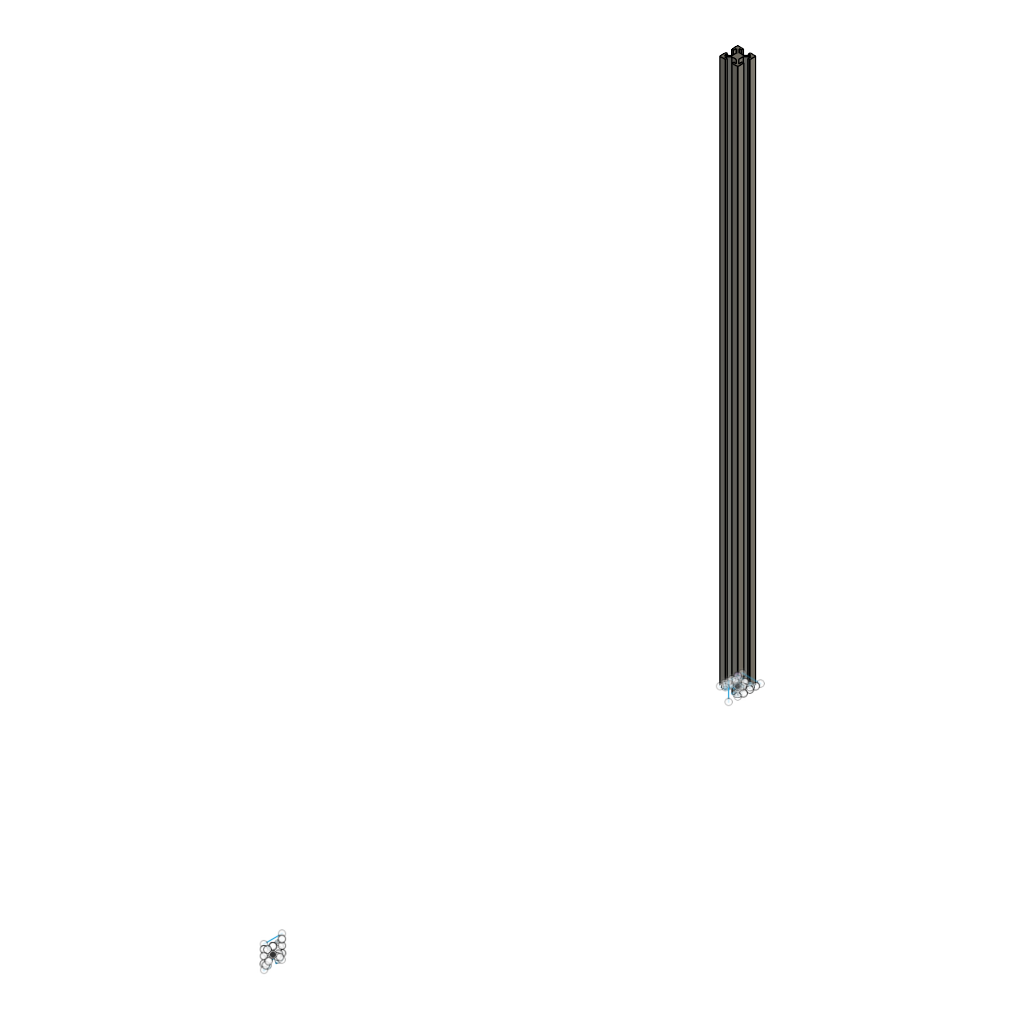
Ensamblaje_TFG (Autodesk Fusion 360 archive; units mm, degrees)
design "Perfilaluminio_23_10_26"
part number: 2026-10-23-16-22-29-947
Autodesk Fusion 360 part; units mm, degrees
sketch "Boceto1" plane through (0, 0, 0) normal (0, 0, 1) x (1, 0, 0)
  line L0 (0, 5) -> (20, 5)
  line L1 (0, -19.75) -> (0, -14.65)
  line L2 (0.25, -20) -> (6.35, -20)
  arc A0 (10, -7.5) -> (10, -12.5) centre (10, -10) ccw
  line L3 (10, -10) -> (10, -7.5) construction
  line L4 (10, -10) -> (10, -12.5) construction
  line L5 (4.1036, -18) -> (6.35, -18)
  line L6 (0, -5.35) -> (0, -6.65)
  arc A1 (0, -6.65) -> (0.25, -6.9) centre (0.25, -6.65) ccw
  line L7 (0, -14.65) -> (0, -13.35)
  arc A2 (0.25, -13.1) -> (0, -13.35) centre (0.25, -13.35) ccw
  line L8 (10, -14) -> (7.5, -14)
  line L9 (10, -6) -> (7.5, -6)
  line L10 (0.25, -6.9) -> (2, -6.9)
  line L11 (0.25, -13.1) -> (2, -13.1)
  line L12 (10, -6) -> (10, -7.5)
  line L13 (10, -12.5) -> (10, -14)
  line L14 (4.1036, -2) -> (6.35, -2)
  line L15 (10, -2) -> (10.0544, -2)
  line L16 (7.5, -10) -> (7.5, -7.5)
  line L17 (7.5, -14) -> (5.4224, -14) construction
  line L18 (6.35, -12.5) -> (5.0376, -12.5) construction
  line L19 (6.35, -2) -> (6.35, 0)
  line L20 (6.35, -20) -> (6.35, -18)
  line L21 (6.35, -12.5) -> (6.35, -7.5)
  line L22 (7.5, -6) -> (3.9268, -2.4268)
  line L23 (7.5, -6) -> (17.1311, -6) construction
  line L24 (6.35, -7.5) -> (2.4268, -3.5768)
  line L25 (6.35, -7.5) -> (15.0863, -7.5) construction
  line L26 (6.35, -12.5) -> (2.4268, -16.4232)
  line L27 (6.35, -12.5) -> (16.6151, -12.5) construction
  line L28 (7.5, -14) -> (3.9268, -17.5732)
  line L29 (7.5, -14) -> (-0.3236, -14) construction
  arc A3 (2.4268, -3.5768) -> (2, -3.7536) centre (2.25, -3.7536) ccw
  arc A4 (4.1036, -2) -> (3.9268, -2.4268) centre (4.1036, -2.25) ccw
  line L30 (2, -3.7536) -> (2, -6.9)
  line L31 (2, -13.1) -> (2, -16.2464)
  arc A5 (2, -16.2464) -> (2.4268, -16.4232) centre (2.25, -16.2464) ccw
  arc A6 (3.9268, -17.5732) -> (4.1036, -18) centre (4.1036, -17.75) ccw
  line L32 (6.35, 0) -> (0.25, 0)
  line L33 (0, -0.25) -> (0, -5.35)
  arc A7 (0.25, 0) -> (0, -0.25) centre (0.25, -0.25) ccw
  arc A8 (0, -19.75) -> (0.25, -20) centre (0.25, -19.75) ccw
  arc A9 (16.0732, -2.4268) -> (15.8964, -2) centre (15.8964, -2.25) ccw
  line L34 (20, -19.75) -> (20, -14.65)
  line L35 (20, -5.35) -> (20, -6.65)
  line L36 (13.65, -7.5) -> (17.5732, -3.5768)
  line L37 (10, -12.5) -> (10, -14)
  line L38 (10, -10) -> (10, -7.5) construction
  line L39 (13.65, 0) -> (19.75, 0)
  line L40 (10, -6) -> (10, -7.5)
  line L41 (10, -10) -> (10, -12.5) construction
  line L42 (12.5, -10) -> (12.5, -7.5)
  line L43 (10, -2) -> (9.9456, -2)
  line L44 (12.5, -14) -> (14.5776, -14) construction
  line L45 (12.5, -6) -> (16.0732, -2.4268)
  line L46 (15.8964, -2) -> (13.65, -2)
  arc A10 (19.75, -20) -> (20, -19.75) centre (19.75, -19.75) ccw
  line L47 (20, -14.65) -> (20, -13.35)
  arc A11 (20, -0.25) -> (19.75, 0) centre (19.75, -0.25) ccw
  arc A12 (19.75, -6.9) -> (20, -6.65) centre (19.75, -6.65) ccw
  arc A13 (17.5732, -16.4232) -> (18, -16.2464) centre (17.75, -16.2464) ccw
  line L48 (19.75, -20) -> (13.65, -20)
  line L49 (13.65, -20) -> (13.65, -18)
  arc A14 (18, -3.7536) -> (17.5732, -3.5768) centre (17.75, -3.7536) ccw
  arc A15 (15.8964, -18) -> (16.0732, -17.5732) centre (15.8964, -17.75) ccw
  line L50 (19.75, -6.9) -> (18, -6.9)
  line L51 (18, -13.1) -> (18, -16.2464)
  line L52 (13.65, -12.5) -> (14.9624, -12.5) construction
  line L53 (13.65, -2) -> (13.65, 0)
  line L54 (15.8964, -18) -> (13.65, -18)
  line L55 (18, -3.7536) -> (18, -6.9)
  line L56 (13.65, -12.5) -> (13.65, -7.5)
  line L57 (12.5, -14) -> (16.0732, -17.5732)
  line L58 (19.75, -13.1) -> (18, -13.1)
  arc A16 (20, -13.35) -> (19.75, -13.1) centre (19.75, -13.35) ccw
  line L59 (20, -0.25) -> (20, -5.35)
  line L60 (12.5, -6) -> (2.8689, -6) construction
  line L61 (10, -14) -> (12.5, -14)
  line L62 (12.5, -14) -> (20.3236, -14) construction
  line L63 (10, -6) -> (12.5, -6)
  line L64 (13.65, -12.5) -> (3.3849, -12.5) construction
  line L65 (13.65, -7.5) -> (4.9137, -7.5) construction
  arc A17 (10, -12.5) -> (10, -7.5) centre (10, -10) ccw
  line L66 (13.65, -12.5) -> (17.5732, -16.4232)
  point P0 (0, -6.35)
  point P1 (20, -6.35)
  point P2 (20, 0)
  dimension "d2" = 6.35
  dimension "d3" = 20
  dimension "d16" = 2.5
  dimension "d17" = 180
  dimension "d27" = 0.25
  dimension "d34" = 135
  dimension "d35" = 135
  dimension "d36" = 135
  dimension "d37" = 45
  dimension "d38" = 0.25
  dimension "d39" = 0.25
  dimension "d40" = 0.25
  dimension "d41" = 0.25
  dimension "d42" = 0.25
  dimension "d43" = 0.25
  constraint vertical L1
  constraint perpendicular L1 L2
  constraint perpendicular L2 L31
  constraint perpendicular L14 L30
  constraint perpendicular L5 L20
  constraint perpendicular L6 L11
  constraint coincident L1.end L6
  constraint tangent L6 A1
  constraint tangent A1 L10
  constraint perpendicular L7 L11
  constraint tangent L7 A2
  constraint perpendicular L8 L20
  constraint perpendicular L9 L19
  constraint perpendicular A0 L12
  constraint perpendicular L8 L13
  constraint collinear L14 L15
  constraint midpoint A0 L16.start
  constraint tangent A0 L16
  constraint perpendicular L9 L16
  constraint horizontal L17
  constraint horizontal L18
  constraint collinear L19 L21
  constraint collinear L20 L21
  constraint horizontal L23
  constraint horizontal L25
  constraint horizontal L27
  constraint horizontal L29
  constraint tangent L24 A3
  constraint tangent A3 L30
  constraint tangent L22 A4
  constraint tangent L14 A4
  constraint collinear L30 L31
  constraint tangent L31 A5
  constraint tangent L26 A5
  constraint tangent L28 A6
  constraint tangent L5 A6
  constraint perpendicular L19 L32
  constraint perpendicular L10 L33
  constraint tangent L32 A7
  constraint tangent L33 A7
  constraint tangent L1 A8
  constraint tangent L2 A8
  constraint symmetric origin L3 P2
  constraint symmetric P0 L3 P1
  constraint symmetric L2.end L3 L48.end
  constraint symmetric A0.start L3 L12.end
  constraint symmetric A0.end L3 L4.end
  constraint symmetric A0 L3 A17
  constraint symmetric L3 L19.end L39.start
  constraint symmetric L3 L15.end L43.end
  constraint symmetric L3 L6.start L35.start
  constraint symmetric L3 L1.end L34.end
  constraint symmetric L3 L6.end L35.end
  constraint symmetric L3 A1.end A12.start
  constraint symmetric L3 A1 A12
  constraint symmetric L3 A2.start L58.start
  constraint symmetric L3 L7.end L47.end
  constraint symmetric L3 A2 A16
  constraint symmetric L3 L8.start L13.end
  constraint symmetric L3 L9.start L12.start
  constraint symmetric L3 L10.end L50.end
  constraint symmetric L3 L11.end L51.start
  constraint symmetric L3 L14.end L46.end
  constraint symmetric L3 L15.start L43.start
  constraint symmetric L3 L5.end L49.end
  constraint symmetric L3 L16.start L42.start
  constraint symmetric L3 L8.end L44.start
  constraint symmetric L3 L9.end L45.start
  constraint symmetric L3 L17.end L44.end
  constraint symmetric L3 L18.start L52.start
  constraint symmetric L3 L21.end L36.start
  constraint symmetric L3 L18.end L52.end
  constraint symmetric L3 L16.end L42.end
  constraint symmetric L3 L23.end L60.end
  constraint symmetric L3 L25.end L65.end
  constraint symmetric L3 L27.end L64.end
  constraint symmetric L3 L29.end L62.end
  constraint symmetric L3 L24.end L36.end
  constraint symmetric L3 A3.end A14.start
  constraint symmetric L3 A3 A14
  constraint symmetric L3 L22.end A9.start
  constraint symmetric L3 L14.start A9.end
  constraint symmetric L3 A4 A9
  constraint symmetric L3 L31.end A13.end
  constraint symmetric L3 L26.end A13.start
  constraint symmetric L3 A5 A13
  constraint symmetric L3 L28.end A15.end
  constraint symmetric L3 L5.start A15.start
  constraint symmetric L3 A6 A15
  constraint symmetric L3 L32.end L39.end
  constraint symmetric L3 L33.start A11.start
  constraint symmetric L3 A7 A11
  constraint symmetric L3 L1.start L34.start
  constraint symmetric L3 L2.start A10.start
  constraint symmetric L3 A8 A10
  measures "d2" distance of origin P0
  measures "d3" distance of L0.start L0.end
  measures "d16" radius of A0
  measures "d17" angle of L3 L4
  measures "d27" radius of A1
  measures "d34" angle of L22 L23
  measures "d35" angle of L24 L25
  measures "d36" angle of L26 L27
  measures "d37" angle of L28 L29
  measures "d38" radius of A3
  measures "d39" radius of A4
  measures "d40" radius of A5
  measures "d41" radius of A6
  measures "d42" radius of A7
  measures "d43" radius of A8
extrude "Extruir1" add sketch "Boceto1" along normal blind 600
sketch "Boceto4" plane through (0, 0, 0) normal (1, 0, 0) x (0, 1, 0)
  line L0 (-521, -14.65) -> (-521, -13.35)
  line L1 (-511, -12.5) -> (-511, -14)
  line L2 (-520.75, -20) -> (-514.65, -20)
  arc A0 (-501.25, -20) -> (-501, -19.75) centre (-501.25, -19.75) ccw
  line L3 (-507.35, -12.5) -> (-517.6151, -12.5) construction
  line L4 (-513.5, -14) -> (-521.3236, -14) construction
  line L5 (-505.1036, -18) -> (-507.35, -18)
  arc A1 (-503.4268, -16.4232) -> (-503, -16.2464) centre (-503.25, -16.2464) ccw
  line L6 (-514.65, -12.5) -> (-515.9624, -12.5) construction
  line L7 (-514.65, -12.5) -> (-518.5732, -16.4232)
  line L8 (-521, -19.75) -> (-521, -14.65)
  line L9 (-511, -10) -> (-511, -7.5) construction
  line L10 (-501, -19.75) -> (-501, -14.65)
  arc A2 (-520.75, -13.1) -> (-521, -13.35) centre (-520.75, -13.35) ccw
  line L11 (-511, -14) -> (-513.5, -14)
  line L12 (-513.5, -14) -> (-517.0732, -17.5732)
  line L13 (-511, -12.5) -> (-511, -14)
  line L14 (-508.5, -14) -> (-504.9268, -17.5732)
  arc A3 (-505.1036, -18) -> (-504.9268, -17.5732) centre (-505.1036, -17.75) ccw
  line L15 (-508.5, -14) -> (-506.4224, -14) construction
  line L16 (-513.5, -14) -> (-515.5776, -14) construction
  line L17 (-501.25, -20) -> (-507.35, -20)
  line L18 (-501, -14.65) -> (-501, -13.35)
  arc A4 (-517.0732, -17.5732) -> (-516.8964, -18) centre (-516.8964, -17.75) ccw
  arc A5 (-519, -16.2464) -> (-518.5732, -16.4232) centre (-518.75, -16.2464) ccw
  line L19 (-511, -14) -> (-508.5, -14)
  arc A6 (-501, -13.35) -> (-501.25, -13.1) centre (-501.25, -13.35) ccw
  arc A7 (-521, -19.75) -> (-520.75, -20) centre (-520.75, -19.75) ccw
  line L20 (-507.35, -12.5) -> (-503.4268, -16.4232)
  line L21 (-519, -13.1) -> (-519, -16.2464)
  line L22 (-507.35, -20) -> (-507.35, -18)
  line L23 (-514.65, -20) -> (-514.65, -18)
  line L24 (-508.5, -14) -> (-500.6764, -14) construction
  line L25 (-516.8964, -18) -> (-514.65, -18)
  line L26 (-507.35, -7.5) -> (-516.0863, -7.5) construction
  line L27 (-511, -2) -> (-511.0544, -2)
  line L28 (-507.35, -7.5) -> (-503.4268, -3.5768)
  line L29 (-511, -6) -> (-513.5, -6)
  arc A8 (-516.8964, -2) -> (-517.0732, -2.4268) centre (-516.8964, -2.25) ccw
  line L30 (-507.35, -2) -> (-507.35, 0)
  arc A9 (-521, -6.65) -> (-520.75, -6.9) centre (-520.75, -6.65) ccw
  line L31 (-520.75, -6.9) -> (-519, -6.9)
  line L32 (-514.65, -7.5) -> (-505.9137, -7.5) construction
  line L33 (-521, -0.25) -> (-521, -5.35)
  line L34 (-511, -2) -> (-510.9456, -2)
  line L35 (-514.65, -2) -> (-514.65, 0)
  line L36 (-503, -13.1) -> (-503, -16.2464)
  line L37 (-507.35, 0) -> (-501.25, 0)
  arc A10 (-501, -0.25) -> (-501.25, 0) centre (-501.25, -0.25) ccw
  line L38 (-501, -0.25) -> (-501, -5.35)
  arc A11 (-504.9268, -2.4268) -> (-505.1036, -2) centre (-505.1036, -2.25) ccw
  line L39 (-514.65, 0) -> (-520.75, 0)
  arc A12 (-520.75, 0) -> (-521, -0.25) centre (-520.75, -0.25) ccw
  line L40 (-501.25, -13.1) -> (-503, -13.1)
  line L41 (-521, 5) -> (-501, 5)
  line L42 (-507.35, -12.5) -> (-506.0376, -12.5) construction
  line L43 (-520.75, -13.1) -> (-519, -13.1)
  line L44 (-514.65, -12.5) -> (-504.3849, -12.5) construction
  line L45 (-513.5, -10) -> (-513.5, -7.5)
  line L46 (-513.5, -6) -> (-503.8689, -6) construction
  line L47 (-516.8964, -2) -> (-514.65, -2)
  line L48 (-508.5, -6) -> (-518.1311, -6) construction
  line L49 (-511, -10) -> (-511, -12.5) construction
  line L50 (-505.1036, -2) -> (-507.35, -2)
  line L51 (-511, -10) -> (-511, -7.5) construction
  line L52 (-513.5, -6) -> (-517.0732, -2.4268)
  arc A13 (-518.5732, -3.5768) -> (-519, -3.7536) centre (-518.75, -3.7536) ccw
  line L53 (-514.65, -12.5) -> (-514.65, -7.5)
  line L54 (-501.25, -6.9) -> (-503, -6.9)
  line L55 (-503, -3.7536) -> (-503, -6.9)
  arc A14 (-511, -7.5) -> (-511, -12.5) centre (-511, -10) ccw
  line L56 (-508.5, -6) -> (-504.9268, -2.4268)
  line L57 (-511, -6) -> (-511, -7.5)
  line L58 (-511, -10) -> (-511, -12.5) construction
  line L59 (-514.65, -7.5) -> (-518.5732, -3.5768)
  line L60 (-507.35, -12.5) -> (-507.35, -7.5)
  arc A15 (-503, -3.7536) -> (-503.4268, -3.5768) centre (-503.25, -3.7536) ccw
  line L61 (-521, -5.35) -> (-521, -6.65)
  line L62 (-508.5, -10) -> (-508.5, -7.5)
  line L63 (-511, -6) -> (-508.5, -6)
  arc A16 (-511, -12.5) -> (-511, -7.5) centre (-511, -10) ccw
  line L64 (-501, -5.35) -> (-501, -6.65)
  arc A17 (-501.25, -6.9) -> (-501, -6.65) centre (-501.25, -6.65) ccw
  line L65 (-511, -6) -> (-511, -7.5)
  line L66 (-519, -3.7536) -> (-519, -6.9)
  line L67 (-10, 0) -> (-10, -20)
  point P0 (-501, -6.35)
  point P1 (-521, 0)
  point P2 (-521, -6.35)
  point P3 (-501, 0)
  dimension "d65" = 6.35
  dimension "d66" = 20
  dimension "d67" = 2.5
  dimension "d68" = 180
  dimension "d69" = 0.25
  dimension "d70" = 135
  dimension "d71" = 135
  dimension "d72" = 135
  dimension "d73" = 45
  dimension "d74" = 0.25
  dimension "d75" = 0.25
  dimension "d76" = 0.25
  dimension "d77" = 0.25
  dimension "d78" = 0.25
  dimension "d79" = 0.25
  dimension "d80" = 20
  constraint vertical L8
  constraint perpendicular L2 L8
  constraint perpendicular L2 L21
  constraint perpendicular L47 L66
  constraint perpendicular L23 L25
  constraint perpendicular L43 L61
  constraint coincident L0.start L61
  constraint tangent A9 L61
  constraint tangent A9 L31
  constraint perpendicular L0 L43
  constraint tangent L0 A2
  constraint perpendicular L11 L23
  constraint perpendicular L29 L35
  constraint perpendicular A14 L65
  constraint perpendicular L11 L13
  constraint collinear L34 L47
  constraint midpoint L45.start A14
  constraint tangent L45 A14
  constraint perpendicular L29 L45
  constraint horizontal L16
  constraint horizontal L6
  constraint collinear L35 L53
  constraint collinear L23 L53
  constraint horizontal L46
  constraint horizontal L32
  constraint horizontal L44
  constraint horizontal L4
  constraint tangent A13 L59
  constraint tangent A13 L66
  constraint tangent A8 L52
  constraint tangent A8 L47
  constraint collinear L21 L66
  constraint tangent A5 L21
  constraint tangent L7 A5
  constraint tangent L12 A4
  constraint tangent A4 L25
  constraint perpendicular L35 L39
  constraint perpendicular L31 L33
  constraint tangent L39 A12
  constraint tangent L33 A12
  constraint tangent L8 A7
  constraint tangent L2 A7
  constraint symmetric P1 P3 L51
  constraint symmetric P0 P2 L51
  constraint symmetric L17.end L2.end L51
  constraint symmetric L9.end A14.start L51
  constraint symmetric L1.start L13.start L51
  constraint symmetric L51 A14 A16
  constraint symmetric L30.end L35.end L51
  constraint symmetric L27.end L34.end L51
  constraint symmetric L38.end L33.end L51
  constraint symmetric L10.end L0.start L51
  constraint symmetric L64.end A9.start L51
  constraint symmetric L54.start A9.end L51
  constraint symmetric A9 L51 A17
  constraint symmetric A6.end A2.start L51
  constraint symmetric L18.end L0.end L51
  constraint symmetric A2 A6 L51
  constraint symmetric L1.end L11.start L51
  constraint symmetric L29.start L57.start L51
  constraint symmetric L31.end L54.end L51
  constraint symmetric L36.start L21.start L51
  constraint symmetric L30.start L35.start L51
  constraint symmetric L27.start L34.start L51
  constraint symmetric L23.end L5.end L51
  constraint symmetric L62.start L45.start L51
  constraint symmetric L14.start L4.start L51
  constraint symmetric L48.start L29.end L51
  constraint symmetric L16.end L15.end L51
  constraint symmetric L3.start L6.start L51
  constraint symmetric L26.start L32.start L51
  constraint symmetric L42.end L6.end L51
  constraint symmetric L62.end L45.end L51
  constraint symmetric L48.end L46.end L51
  constraint symmetric L26.end L32.end L51
  constraint symmetric L3.end L44.end L51
  constraint symmetric L24.end L4.end L51
  constraint symmetric L28.end A13.start L51
  constraint symmetric L55.start A13.end L51
  constraint symmetric L51 A13 A15
  constraint symmetric A11.start A8.end L51
  constraint symmetric A8.start A11.end L51
  constraint symmetric A8 A11 L51
  constraint symmetric A1.end A5.start L51
  constraint symmetric A1.start L7.end L51
  constraint symmetric A1 A5 L51
  constraint symmetric L14.end L12.end L51
  constraint symmetric L5.start A4.end L51
  constraint symmetric A3 A4 L51
  constraint symmetric L39.end L37.end L51
  constraint symmetric A10.start L33.start L51
  constraint symmetric A10 A12 L51
  constraint symmetric A0.end L8.start L51
  constraint symmetric A0.start L2.start L51
  constraint symmetric A0 A7 L51
  constraint vertical L67
  measures "d65" distance of P1 P2
  measures "d66" distance of L41.end L41.start
  measures "d67" radius of A14
  measures "d68" angle of L51 L58
  measures "d69" radius of A9
  measures "d70" angle of L46 L52
  measures "d71" angle of L32 L59
  measures "d72" angle of L7 L44
  measures "d73" angle of L4 L12
  measures "d74" radius of A13
  measures "d75" radius of A8
  measures "d76" radius of A5
  measures "d77" radius of A4
  measures "d78" radius of A12
  measures "d79" radius of A7
  measures "d80" distance of L67.start L67.end
